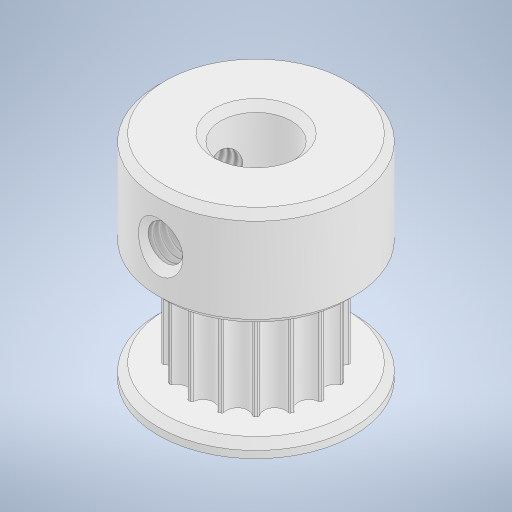
# Autodesk Inventor part: GT2 16T Pulley
Saved by Autodesk Inventor 2024.1 (Build 281209000, 209)
## iProperties
Created: 2023-07-07
Part Number: GT2 16T Pulley
Material: ABS Plastic
Document SubType Name: Modeling
Designer: Jeroen
Density: 1.06 g/cm^3
Appearance: Smooth - White
Mass: 1.30237 g
Surface Area: 13.1857 cm^2
Volume: 1.22865 cm^3
Author: Jeroen
Autodesk Inventor part; units mm, degrees
ref_plane "YZ Plane" through (0, 0, 0) normal (1, 0, 0) x (0, 1, 0)
sketch "Sketch1" plane through (0, 0, 0) normal (0, 0, 1) x (1, 0, 0)
  line L0 (0, 0) -> (15, 0)
  line L1 (0, 0) -> (0, 6.9)
  line L2 (0, 6.9) -> (7, 6.9)
  line L3 (7, 6.9) -> (7, 4)
  line L4 (7, 4) -> (14, 4)
  line L5 (14, 4) -> (14, 6.9)
  line L6 (14, 6.9) -> (15, 6.9)
  line L7 (15, 2.5) -> (0, 2.5)
  line L8 (15, 2.5) -> (15, 3.8557)
  line L9 (15, 3.8557) -> (14.75, 4)
  line L10 (14.75, 4) -> (15, 4.1443)
  line L11 (15, 4.1443) -> (15, 6.9)
  line L12 (14, 4) -> (14.75, 4)
  dimension "d0" = 15
  dimension "d1" = 7
  dimension "d2" = 1
  dimension "d3" = 13.8
  dimension "d4" = 5
  dimension "d5" = 8
  dimension "d37" = 60
  dimension "d38" = 0.25
  dimension "d39" = 15
  constraints: 26 end point, 6 perpendicular, 3 horizontal, 2 collinear, 2 point on line, 1 equal length, 1 vertical
  measures "d0" distance of L0.start L0.end
  measures "d1" distance of L1.end L2.end
  measures "d2" distance of L5.end L6.end
  measures "d3" diameter of L2 L0
  measures "d4" diameter of L7 L0
  measures "d5" diameter of L4 L0
  measures "d37" angle of L10 L9
  measures "d38" horizontal distance of L8.end L9.end
  measures "d39" distance between parallel lines of L11 L1
revolve "Revolution1" add sketch "Sketch1" angle 360 about axis through (0, 0, 0) along (1, 0, 0)
ref_plane "Work Plane1" through (0, 0, 6.9) normal (0, 0, 1) x (1, 0, 0)
ref_plane "Work Plane2" through (0, 6.9, 0) normal (0, 1, 0) x (-1, 0, 0)
sketch "Sketch2" plane through (0, 0, 6.9) normal (0, 0, 1) x (1, 0, 0)
  line L0 (0, -6.9) -> (0, 6.9) construction
  line L1 (7, -6.9) -> (7, 6.9) construction
  line L2 (0, -6.9) -> (7, -6.9) construction
  line L3 (0, 6.9) -> (7, 6.9) construction
  line L4 (3.5, -6.9) -> (3.5, 6.9) construction
  point P0 (0, 0)
  point P1 (3.5, 0)
  constraints: 3 midpoint, 2 end point
sketch "Sketch3" plane through (0, 6.9, 0) normal (0, 1, 0) x (-1, 0, 0)
  line L0 (0, -6.9) -> (-7, -6.9) construction
  line L1 (0, 6.9) -> (0, -6.9) construction
  line L2 (-7, 6.9) -> (-7, -6.9) construction
  line L3 (0, 6.9) -> (-7, 6.9) construction
  line L4 (-3.5, -6.9) -> (-3.5, 6.9) construction
  line L5 (0, 6.9) -> (-7, 6.9) construction
  point P0 (0, 0)
  point P1 (-3.5, 0)
  constraints: 3 midpoint, 2 end point
hole "Hole1" at (3.5, 6.9, 0) direction (0, -1, 0) diameter 2.459 end up to surface countersink diameter 3.5 countersink angle 90 thread size "M3x0.5" class "6H" standard "ISO Metric profile"
hole "Hole2" at (3.5, 0, 6.9) direction (0, 0, -1) diameter 2.459 end up to surface countersink diameter 3.5 countersink angle 90 thread size "M3x0.5" class "6H" standard "ISO Metric profile"
chamfer "Chamfer1" distance 0.5 angle 45 5 edges at (0, -6.9, 0) (7, -6.9, 0) (14, -6.9, 0) (0, -2.5, 0) (15, -2.5, 0)
sketch "Sketch5" plane through (7, 0, 0) normal (1, 0, 0) x (0, 0, -1)
  circle A0 centre (0, 0) radius 4 projected
  arc A1 (0.072, 4.6994) -> (-0.072, 4.6994) centre (0, 0) ccw
  line L0 (0, 4.7) -> (0, 0) construction
  arc A2 (-0.7804, 3.9231) -> (-0.1702, 4.6076) centre (-0.9289, 4.6698) ccw
  arc A3 (0.1702, 4.6076) -> (0.7804, 3.9231) centre (0.9289, 4.6698) ccw
  arc A4 (-0.072, 4.6994) -> (-0.1702, 4.6076) centre (-0.0705, 4.5995) ccw
  arc A5 (0.1702, 4.6076) -> (0.072, 4.6994) centre (0.0705, 4.5995) ccw
  arc A6 (-1.7319, 4.3693) -> (-1.8649, 4.3142) centre (0, 0) ccw
  arc A7 (-2.2223, 3.3259) -> (-1.9205, 4.1918) centre (-2.6452, 3.9588) ccw
  arc A8 (-1.606, 4.322) -> (-0.7804, 3.9231) centre (-0.9289, 4.6698) ccw
  arc A9 (-1.8649, 4.3142) -> (-1.9205, 4.1918) centre (-1.8253, 4.2224) ccw
  arc A10 (-1.606, 4.322) -> (-1.7319, 4.3693) centre (-1.695, 4.2763) ccw
  arc A11 (-3.2721, 3.3739) -> (-3.3739, 3.2721) centre (0, 0) ccw
  arc A12 (-3.3259, 2.2223) -> (-3.3784, 3.1378) centre (-3.9588, 2.6452) ccw
  arc A13 (-3.1378, 3.3784) -> (-2.2223, 3.3259) centre (-2.6452, 3.9588) ccw
  arc A14 (-3.3739, 3.2721) -> (-3.3784, 3.1378) centre (-3.3022, 3.2025) ccw
  arc A15 (-3.1378, 3.3784) -> (-3.2721, 3.3739) centre (-3.2025, 3.3022) ccw
  arc A16 (-4.3142, 1.8649) -> (-4.3693, 1.7319) centre (0, 0) ccw
  arc A17 (-3.9231, 0.7804) -> (-4.322, 1.606) centre (-4.6698, 0.9289) ccw
  arc A18 (-4.1918, 1.9205) -> (-3.3259, 2.2223) centre (-3.9588, 2.6452) ccw
  arc A19 (-4.3693, 1.7319) -> (-4.322, 1.606) centre (-4.2763, 1.695) ccw
  arc A20 (-4.1918, 1.9205) -> (-4.3142, 1.8649) centre (-4.2224, 1.8253) ccw
  arc A21 (-4.6994, 0.072) -> (-4.6994, -0.072) centre (0, 0) ccw
  arc A22 (-3.9231, -0.7804) -> (-4.6076, -0.1702) centre (-4.6698, -0.9289) ccw
  arc A23 (-4.6076, 0.1702) -> (-3.9231, 0.7804) centre (-4.6698, 0.9289) ccw
  arc A24 (-4.6994, -0.072) -> (-4.6076, -0.1702) centre (-4.5995, -0.0705) ccw
  arc A25 (-4.6076, 0.1702) -> (-4.6994, 0.072) centre (-4.5995, 0.0705) ccw
  arc A26 (-4.3693, -1.7319) -> (-4.3142, -1.8649) centre (0, 0) ccw
  arc A27 (-3.3259, -2.2223) -> (-4.1918, -1.9205) centre (-3.9588, -2.6452) ccw
  arc A28 (-4.322, -1.606) -> (-3.9231, -0.7804) centre (-4.6698, -0.9289) ccw
  arc A29 (-4.3142, -1.8649) -> (-4.1918, -1.9205) centre (-4.2224, -1.8253) ccw
  arc A30 (-4.322, -1.606) -> (-4.3693, -1.7319) centre (-4.2763, -1.695) ccw
  arc A31 (-3.3739, -3.2721) -> (-3.2721, -3.3739) centre (0, 0) ccw
  arc A32 (-2.2223, -3.3259) -> (-3.1378, -3.3784) centre (-2.6452, -3.9588) ccw
  arc A33 (-3.3784, -3.1378) -> (-3.3259, -2.2223) centre (-3.9588, -2.6452) ccw
  arc A34 (-3.2721, -3.3739) -> (-3.1378, -3.3784) centre (-3.2025, -3.3022) ccw
  arc A35 (-3.3784, -3.1378) -> (-3.3739, -3.2721) centre (-3.3022, -3.2025) ccw
  arc A36 (-1.8649, -4.3142) -> (-1.7319, -4.3693) centre (0, 0) ccw
  arc A37 (-0.7804, -3.9231) -> (-1.606, -4.322) centre (-0.9289, -4.6698) ccw
  arc A38 (-1.9205, -4.1918) -> (-2.2223, -3.3259) centre (-2.6452, -3.9588) ccw
  arc A39 (-1.7319, -4.3693) -> (-1.606, -4.322) centre (-1.695, -4.2763) ccw
  arc A40 (-1.9205, -4.1918) -> (-1.8649, -4.3142) centre (-1.8253, -4.2224) ccw
  arc A41 (-0.072, -4.6994) -> (0.072, -4.6994) centre (0, 0) ccw
  arc A42 (0.7804, -3.9231) -> (0.1702, -4.6076) centre (0.9289, -4.6698) ccw
  arc A43 (-0.1702, -4.6076) -> (-0.7804, -3.9231) centre (-0.9289, -4.6698) ccw
  arc A44 (0.072, -4.6994) -> (0.1702, -4.6076) centre (0.0705, -4.5995) ccw
  arc A45 (-0.1702, -4.6076) -> (-0.072, -4.6994) centre (-0.0705, -4.5995) ccw
  arc A46 (1.7319, -4.3693) -> (1.8649, -4.3142) centre (0, 0) ccw
  arc A47 (2.2223, -3.3259) -> (1.9205, -4.1918) centre (2.6452, -3.9588) ccw
  arc A48 (1.606, -4.322) -> (0.7804, -3.9231) centre (0.9289, -4.6698) ccw
  arc A49 (1.8649, -4.3142) -> (1.9205, -4.1918) centre (1.8253, -4.2224) ccw
  arc A50 (1.606, -4.322) -> (1.7319, -4.3693) centre (1.695, -4.2763) ccw
  arc A51 (3.2721, -3.3739) -> (3.3739, -3.2721) centre (0, 0) ccw
  arc A52 (3.3259, -2.2223) -> (3.3784, -3.1378) centre (3.9588, -2.6452) ccw
  arc A53 (3.1378, -3.3784) -> (2.2223, -3.3259) centre (2.6452, -3.9588) ccw
  arc A54 (3.3739, -3.2721) -> (3.3784, -3.1378) centre (3.3022, -3.2025) ccw
  arc A55 (3.1378, -3.3784) -> (3.2721, -3.3739) centre (3.2025, -3.3022) ccw
  arc A56 (4.3142, -1.8649) -> (4.3693, -1.7319) centre (0, 0) ccw
  arc A57 (3.9231, -0.7804) -> (4.322, -1.606) centre (4.6698, -0.9289) ccw
  arc A58 (4.1918, -1.9205) -> (3.3259, -2.2223) centre (3.9588, -2.6452) ccw
  arc A59 (4.3693, -1.7319) -> (4.322, -1.606) centre (4.2763, -1.695) ccw
  arc A60 (4.1918, -1.9205) -> (4.3142, -1.8649) centre (4.2224, -1.8253) ccw
  arc A61 (4.6994, -0.072) -> (4.6994, 0.072) centre (0, 0) ccw
  arc A62 (3.9231, 0.7804) -> (4.6076, 0.1702) centre (4.6698, 0.9289) ccw
  arc A63 (4.6076, -0.1702) -> (3.9231, -0.7804) centre (4.6698, -0.9289) ccw
  arc A64 (4.6994, 0.072) -> (4.6076, 0.1702) centre (4.5995, 0.0705) ccw
  arc A65 (4.6076, -0.1702) -> (4.6994, -0.072) centre (4.5995, -0.0705) ccw
  arc A66 (4.3693, 1.7319) -> (4.3142, 1.8649) centre (0, 0) ccw
  arc A67 (3.3259, 2.2223) -> (4.1918, 1.9205) centre (3.9588, 2.6452) ccw
  arc A68 (4.322, 1.606) -> (3.9231, 0.7804) centre (4.6698, 0.9289) ccw
  arc A69 (4.3142, 1.8649) -> (4.1918, 1.9205) centre (4.2224, 1.8253) ccw
  arc A70 (4.322, 1.606) -> (4.3693, 1.7319) centre (4.2763, 1.695) ccw
  arc A71 (3.3739, 3.2721) -> (3.2721, 3.3739) centre (0, 0) ccw
  arc A72 (2.2223, 3.3259) -> (3.1378, 3.3784) centre (2.6452, 3.9588) ccw
  arc A73 (3.3784, 3.1378) -> (3.3259, 2.2223) centre (3.9588, 2.6452) ccw
  arc A74 (3.2721, 3.3739) -> (3.1378, 3.3784) centre (3.2025, 3.3022) ccw
  arc A75 (3.3784, 3.1378) -> (3.3739, 3.2721) centre (3.3022, 3.2025) ccw
  arc A76 (1.8649, 4.3142) -> (1.7319, 4.3693) centre (0, 0) ccw
  arc A77 (0.7804, 3.9231) -> (1.606, 4.322) centre (0.9289, 4.6698) ccw
  arc A78 (1.9205, 4.1918) -> (2.2223, 3.3259) centre (2.6452, 3.9588) ccw
  arc A79 (1.7319, 4.3693) -> (1.606, 4.322) centre (1.695, 4.2763) ccw
  arc A80 (1.9205, 4.1918) -> (1.8649, 4.3142) centre (1.8253, 4.2224) ccw
  arc A81 (-0.1702, 4.6076) -> (-1.606, 4.322) centre (-0.9289, 4.6698) ccw
  arc A82 (-1.9205, 4.1918) -> (-3.1378, 3.3784) centre (-2.6452, 3.9588) ccw
  arc A83 (-3.3784, 3.1378) -> (-4.1918, 1.9205) centre (-3.9588, 2.6452) ccw
  arc A84 (-4.322, 1.606) -> (-4.6076, 0.1702) centre (-4.6698, 0.9289) ccw
  arc A85 (-4.6076, -0.1702) -> (-4.322, -1.606) centre (-4.6698, -0.9289) ccw
  arc A86 (-4.1918, -1.9205) -> (-3.3784, -3.1378) centre (-3.9588, -2.6452) ccw
  arc A87 (-3.1378, -3.3784) -> (-1.9205, -4.1918) centre (-2.6452, -3.9588) ccw
  arc A88 (-1.606, -4.322) -> (-0.1702, -4.6076) centre (-0.9289, -4.6698) ccw
  arc A89 (0.1702, -4.6076) -> (1.606, -4.322) centre (0.9289, -4.6698) ccw
  arc A90 (1.9205, -4.1918) -> (3.1378, -3.3784) centre (2.6452, -3.9588) ccw
  arc A91 (3.3784, -3.1378) -> (4.1918, -1.9205) centre (3.9588, -2.6452) ccw
  arc A92 (4.322, -1.606) -> (4.6076, -0.1702) centre (4.6698, -0.9289) ccw
  arc A93 (4.6076, 0.1702) -> (4.322, 1.606) centre (4.6698, 0.9289) ccw
  arc A94 (4.1918, 1.9205) -> (3.3784, 3.1378) centre (3.9588, 2.6452) ccw
  arc A95 (3.1378, 3.3784) -> (1.9205, 4.1918) centre (2.6452, 3.9588) ccw
  arc A96 (1.606, 4.322) -> (0.1702, 4.6076) centre (0.9289, 4.6698) ccw
  point P0 (-1.7986, 4.3422)
  point P1 (-3.3234, 3.3234)
  point P2 (-4.3422, 1.7986)
  point P3 (-4.7, 0)
  point P4 (-4.3422, -1.7986)
  point P5 (-3.3234, -3.3234)
  point P6 (-1.7986, -4.3422)
  point P7 (0, -4.7)
  point P8 (1.7986, -4.3422)
  point P9 (3.3234, -3.3234)
  point P10 (4.3422, -1.7986)
  point P11 (4.7, 0)
  point P12 (4.3422, 1.7986)
  point P13 (3.3234, 3.3234)
  point P14 (1.7986, 4.3422)
  point P15 (0.7804, 3.9231)
  point P16 (0.7804, 3.9231)
  point P17 (0.7804, 3.9231)
  point P18 (2.2223, 3.3259)
  point P19 (2.2223, 3.3259)
  point P20 (2.2223, 3.3259)
  point P21 (3.9231, -0.7804)
  point P22 (3.9231, -0.7804)
  point P23 (3.9231, -0.7804)
  point P24 (0.7804, -3.9231)
  point P25 (0.7804, -3.9231)
  point P26 (0.7804, -3.9231)
  point P27 (-0.7804, -3.9231)
  point P28 (-0.7804, -3.9231)
  point P29 (-0.7804, -3.9231)
  point P30 (-2.2223, -3.3259)
  point P31 (-2.2223, -3.3259)
  point P32 (-2.2223, -3.3259)
  point P33 (-3.3259, -2.2223)
  point P34 (-3.3259, -2.2223)
  point P35 (-3.3259, -2.2223)
  point P36 (-3.9231, -0.7804)
  point P37 (-3.9231, -0.7804)
  point P38 (-3.9231, -0.7804)
  point P39 (-3.9231, 0.7804)
  point P40 (-3.9231, 0.7804)
  point P41 (-3.9231, 0.7804)
  point P42 (-3.3259, 2.2223)
  point P43 (-3.3259, 2.2223)
  point P44 (-3.3259, 2.2223)
  point P45 (-2.2223, 3.3259)
  point P46 (-2.2223, 3.3259)
  point P47 (-2.2223, 3.3259)
  point P48 (-0.7804, 3.9231)
  point P49 (-0.7804, 3.9231)
  point P50 (-4.6076, -0.1702)
  point P51 (-4.322, -1.606)
  point P52 (-4.1918, -1.9205)
  point P53 (-3.3784, -3.1378)
  point P54 (-3.1378, -3.3784)
  point P55 (-1.9205, -4.1918)
  point P56 (-1.606, -4.322)
  point P57 (-0.1702, -4.6076)
  point P58 (0.1702, -4.6076)
  point P59 (1.606, -4.322)
  point P60 (1.9205, -4.1918)
  point P61 (3.1378, -3.3784)
  point P62 (3.3784, -3.1378)
  point P63 (4.1918, -1.9205)
  point P64 (4.322, -1.606)
  point P65 (4.6076, -0.1702)
  point P66 (4.6076, 0.1702)
  point P67 (4.322, 1.606)
  point P68 (4.1918, 1.9205)
  point P69 (3.3784, 3.1378)
  point P70 (3.1378, 3.3784)
  point P71 (1.9205, 4.1918)
  point P72 (1.606, 4.322)
  point P73 (0.1702, 4.6076)
  point P74 (-1.9205, 4.1918)
  point P75 (-3.1378, 3.3784)
  point P76 (-4.322, 1.606)
  point P77 (-4.6076, 0.1702)
  point P78 (-3.3784, 3.1378)
  point P79 (-4.1918, 1.9205)
  dimension "d40" = 4.7
  dimension "d44" = 360
  dimension "d46" = 0.1
  dimension "d51" = 360
  constraints: 193 point on circle, 96 centre point, 3 coincident, 3 symmetric about line, 3 tangent, 2 end point, 1 vertical, 343 other
  measures "d40" radius of A1
  measures "d46" radius of A4
extrude "Extrusion2" add sketch "Sketch5" along normal up to surface (7 mm away) contours A0 A62 A64 A61 A65 A63 | A0 A67 A69 A66 A70 A68 | A57 A59 A56 A60 A58 A0 | A0 A72 A74 A71 A75 A73 | A52 A54 A51 A55 A53 A0 | A0 A77 A79 A76 A80 A78 | A47 A49 A46 A50 A48 A0 | A0 A2 A4 A1 A5 A3 | A42 A44 A41 A45 A43 A0 | A0 A7 A9 A6 A10 A8 | A37 A39 A36 A40 A38 A0 | A0 A12 A14 A11 A15 A13 | A32 A34 A31 A35 A33 A0 | A0 A17 A19 A16 A20 A18 | A27 A29 A26 A30 A28 A0 | A0 A22 A24 A21 A25 A23
extrude "Extrusion3" cut sketch "Sketch5" against normal blind 0.2 contours A88 A37 A43 | A84 A17 A23 | A96 A77 A3 | A68 A93 A62 | A63 A92 A57 | A73 A94 A67 | A58 A91 A52 | A78 A95 A72 | A53 A90 A47 | A48 A89 A42 | A8 A81 A2 | A13 A82 A7 | A38 A87 A32 | A18 A83 A12 | A33 A86 A27 | A28 A85 A22
body "Solid1"
